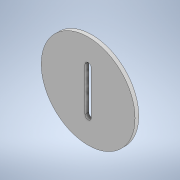
# Autodesk Inventor part: 4_1_capac_nr_1_6_mm
Saved by Autodesk Inventor 2022.6 (Build 266554000, 554)
## iProperties
Created: 2025-09-01
Part Number: 4_1_capac_nr_1_6_mm
Material: Generic
Document SubType Name: Modeling
Designer: Dragos Macovei
Density: 1 g/cm^3
Appearance: Default
Author: Dragos Macovei
Autodesk Inventor part; units mm, degrees
ref_plane "YZ Plane" through (0, 0, 0) normal (1, 0, 0) x (0, 1, 0)
ref_plane "XZ Plane" through (0, 0, 0) normal (0, 1, 0) x (-1, 0, 0)
ref_plane "XY Plane" through (0, 0, 0) normal (0, 0, 1) x (1, 0, 0)
sketch "Sketch1" plane through (0, 0, 0) normal (0, 0, 1) x (1, 0, 0)
  circle A0 centre (0, 0) radius 75
  dimension "d0" = 150
  constraints: 1 centre point, 1 coincident
  measures "d0" diameter of A0
extrude "Extrusion1" add sketch "Sketch1" along normal blind 6
sketch "Sketch2" plane through (0, 0, 6) normal (0, 0, 1) x (1, 0, 0)
  circle A0 centre (0, 0) radius 60 construction
  line L0 (-40, 44.7214) -> (40, 44.7214)
  line L1 (40, 44.7214) -> (40, -44.7214)
  line L2 (40, -44.7214) -> (-40, -44.7214)
  line L3 (-40, -44.7214) -> (-40, 44.7214)
  circle A1 centre (0, -34.7214) radius 5
  line L4 (5, -34.7214) -> (5, 34.7214)
  line L5 (-5, 34.7214) -> (-5, -34.7214)
  circle A2 centre (0, 34.7214) radius 5
  point P0 (0, 44.7214)
  dimension "d3" = 120
  dimension "d16" = 10
  dimension "d17" = 10
  dimension "d20" = 10
  dimension "d21" = 10
  dimension "d29" = 0
  constraints: 12 end point, 7 point on circle, 4 tangent, 3 centre point, 2 parallel, 1 coincident, 1 horizontal, 1 midpoint, 1 perpendicular
  measures "d3" diameter of A0
  measures "d16" diameter of A2
  measures "d17" diameter of A1
  measures "d20" distance from line of A2.centre L0
  measures "d21" distance from line of A1.centre L2
  measures "d29" horizontal distance of point (0, 44.721) A2.centre
extrude "Extrusion2" cut sketch "Sketch2" against normal through all contours A1 | A1 L5 A2 L4 | A2
body "Solid1"
